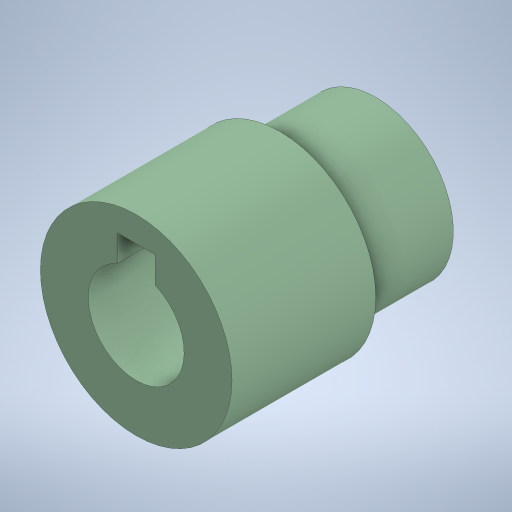
# Autodesk Inventor part: Gear1(input)
Saved by Autodesk Inventor 2023 (Build 270158000, 158)
## iProperties
Created: 2024-05-11
Part Number: Gear1(input)
Material: Generic
Document SubType Name: Modeling
Designer: BenFr
Density: 1 g/cm^3
Appearance: Rubber - Green
Author: BenFr
Autodesk Inventor part; units mm, degrees
ref_plane "YZ Plane" through (0, 0, 0) normal (1, 0, 0) x (0, 1, 0)
ref_plane "XZ Plane" through (0, 0, 0) normal (0, 1, 0) x (-1, 0, 0)
ref_plane "XY Plane" through (0, 0, 0) normal (0, 0, 1) x (1, 0, 0)
sketch "Sketch2" plane through (0, 0, 0) normal (0, 1, 0) x (-1, 0, 0)
  line L0 (0, 0) -> (12.7, 0)
  line L1 (12.7, 0) -> (12.7, -19.05)
  line L2 (0, 0) -> (0, -31.75)
  line L3 (0, -31.75) -> (10.285, -31.75)
  line L4 (10.285, -31.75) -> (10.285, -19.05)
  line L5 (10.285, -19.05) -> (12.7, -19.05)
  line L6 (0, 0) -> (6.35, 0)
  line L7 (6.35, 0) -> (6.35, -31.75)
  dimension "d0" = 12.7
  dimension "d1" = 19.05
  dimension "d2" = 31.75
  dimension "d3" = 10.285
  dimension "d4" = 6.35
  constraints: 16 end point, 4 perpendicular, 2 vertical, 1 horizontal, 1 midpoint, 1 point on line
  measures "d0" distance of L0.start L0.end
  measures "d1" distance of L0.end L1.end
  measures "d2" distance of L0.start L2.end
  measures "d3" distance of L2.end L3.end
  measures "d4" distance of L0.start L6.end
revolve "Revolution1" add sketch "Sketch2" angle 360 about axis through (0, 0, 0) along (0, 0, -1) contours L0 L1 L5 L4 L3 L7
sketch "Sketch3" plane through (0, 0, 0) normal (0, 0, 1) x (1, 0, 0)
  line L0 (-2.5, 3.35) -> (2.5, 3.35)
  line L1 (2.5, 3.35) -> (2.5, 9.35)
  line L2 (2.5, 9.35) -> (-2.5, 9.35)
  line L3 (-2.5, 9.35) -> (-2.5, 3.35)
  circle A0 centre (0, 0) radius 6.35 projected
  line L4 (-2.5, 3.35) -> (2.5, 9.35) construction
  line L5 (2.5, 3.35) -> (-2.5, 9.35) construction
  point P0 (0, 6.35)
  dimension "d6" = 5
  dimension "d7" = 6
  constraints: 12 end point, 2 midpoint, 2 parallel, 1 horizontal, 1 perpendicular, 1 vertical alignment, 1 other
  measures "d6" distance of L2.end L1.end
  measures "d7" distance of L1.end L0.end
extrude "Extrusion1" cut sketch "Sketch3" against normal through all contours L3 A0 L1 L0 | L3 L2 L1 A0 picked at (0, 4.35)
body "Solid1"
